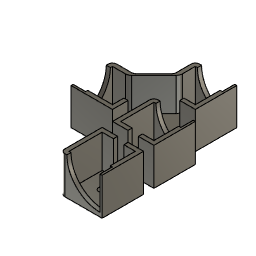
LedCorner15.5v13 (Autodesk Fusion 360 design; units mm, degrees)
Autodesk Fusion 360 part; units mm, degrees
sketch "Sketch1" plane through (0, 0, 0) normal (0, 0, 1) x (1, 0, 0)
  line L0 (0, 0) -> (20, 0)
  line L1 (20, 0) -> (20, 20)
  circle A0 centre (10, 10) radius 1.7
  line L2 (20, 10) -> (10, 10) construction
  line L3 (10, 0) -> (10, 10) construction
  line L4 (-4.9497, 4.9497) -> (0, 0)
  line L5 (12.5, 2) -> (12.5, 0)
  circle A1 centre (10, 10) radius 2.7
  line L6 (-0.5858, 9.3137) -> (-4.9497, 4.9497)
  line L7 (0, 18) -> (0, 10.7279)
  line L8 (2, 20) -> (20, 20)
  line L9 (18, 2) -> (18, 18)
  line L10 (2, 18) -> (18, 18)
  line L11 (2, 18) -> (2, 11.7279)
  line L12 (1.1213, 9.6066) -> (-4.2426, 4.2426)
  arc A2 (-0.5858, 9.3137) -> (0, 10.7279) centre (-2, 10.7279) ccw
  arc A3 (1.1213, 9.6066) -> (2, 11.7279) centre (-1, 11.7279) ccw
  line L13 (12.5, 2) -> (18, 2)
  arc A4 (2, 20) -> (0, 18) centre (2, 18) ccw
  line L14 (0, 13) -> (0, 0)
  line L15 (2, 13.8477) -> (2, 2)
  line L16 (2, 2) -> (7.5, 2)
  line L17 (7.5, 2) -> (7.5, 0)
  dimension "d4" = 3.4
  dimension "d28" = 2.5
  dimension "d29" = 135
  dimension "d33" = 1
  dimension "d35" = 7
  dimension "d49" = 2
  dimension "d50" = 3
  dimension "d52" = 2
  dimension "d53" = 2
  dimension "d54" = 20
  dimension "d55" = 20
  dimension "d57" = 2
  dimension "d58" = 2
  dimension "d59" = 1
  dimension "d60" = 2
  dimension "d67" = 2.5
  dimension "d68" = 2
  constraint coincident L0.start L4.end
  constraint horizontal L0
  constraint perpendicular L0 L1
  constraint midpoint L1 L2.start
  constraint coincident A0.centre L2.end
  constraint perpendicular L1 L2
  constraint midpoint L0 L3.start
  constraint perpendicular L0 L3
  constraint coincident L0 L5.end
  constraint perpendicular L0 L5
  constraint symmetric L6.end L4 L4.start
  constraint parallel L1 L9
  constraint parallel L8 L10
  constraint parallel L7 L11
  constraint parallel L6 L12
  constraint tangent L7 A2
  constraint tangent L6 A2
  constraint tangent L11 A3
  constraint tangent L12 A3
  constraint coincident L1.end L8.end
  constraint horizontal L8
  constraint tangent L8 A4
  constraint tangent L7 A4
  constraint perpendicular L4 L12
  constraint horizontal L13
  constraint coincident L4 L12.end
  constraint vertical L0.start L7.start
  constraint coincident L7 L14.start
  constraint perpendicular L0 L14
  constraint coincident L11 L15.start
  constraint perpendicular L13 L15
  constraint perpendicular L3 L16
  constraint perpendicular L0 L17
  constraint coincident L0 L17.end
  measures "d4" diameter of A0
  measures "d28" horizontal distance of A0.centre L5.start
  measures "d29" angle of L0 L4
  measures "d35" distance of L4.start L0.start
  measures "d49" radius of A2
  measures "d50" radius of A3
  measures "d52" distance of L5.start L5.end
  measures "d53" distance of L1 L9
  measures "d54" distance of L0.end L1.end
  measures "d55" distance of L1 L7
  measures "d57" distance of L8 L10
  measures "d58" distance of L7 L11
  measures "d59" distance of L6 L12
  measures "d60" radius of A4
  measures "d67" distance of L3 L16.end
  measures "d68" distance of L16.end L17.end
extrude "Extrude1" add sketch "Sketch1" along normal blind 2 contours L0 L12 A3 L14 L15 L16 L17 | L4 L12 L14 | L0 L5 L9 L10 L11 L13 L15 L16 L17 | L4 L6 L12 A2 L14 | L0 L1 L5 L7 L8 L9 L10 L11 L12 A3 L13 A4 L14 L15 | A1 makes body 1
extrude "Extrude2" add sketch "Sketch1" along normal blind 18 contours L4 L6 L12 A2 L14 | L0 L1 L5 L7 L8 L9 L10 L11 L12 A3 L13 A4 L14 L15 bodies 1
sketch "Sketch4" plane through (0, 20, 0) normal (0, 1, 0) x (-1, 0, 0)
  line L0 (-19, 18) -> (-19, 0.1056)
  arc A0 (-19, 2) -> (-3, 18) centre (-19, 18) ccw
  line L1 (-19, 18) -> (-3, 18)
  point P0 (-20, 18)
  dimension "d41" = 16
  dimension "d63" = 1
  constraint vertical L0
  constraint coincident L0 A0.start
  constraint coincident L0.start A0.centre
  constraint horizontal L1
  measures "d41" radius of A0
  measures "d63" distance of L0.start P0
extrude "Extrude7" cut sketch "Sketch4" against normal blind 6 bodies 1
mirror "Mirror1" about plane through (-4.2426, 4.2426, 0) normal (-0.707107, -0.707107, 0) of bodies 1 merged
chamfer "Chamfer2" distance 0.4 angle 45 11 edges at (0, 14.364, 0) (-0.1522, 9.9626, 0) (-4.9497, 4.9497, 0) (-9.9626, 0.1522, 0) (-14.364, 0, 0) (-19.4142, -0.5858, 0) (-20, -11, 0) (11, 20, 0) (0.5858, 19.4142, 0) (-10, -20, 0) (20, 10, 0) on bodies 1
fillet "Fillet2" radius 1 1 edges at (0, 0, 1) on bodies 1
copy_body "Body->Comp2" bodies 1 removing the originals makes body 2 in component "Corner"
move_body "Move1" bodies 2 to x (1, 0, 0) y (0, 1, 0) z (0, 0, 1) at (-5, 25, 0) in component "Corner"
extrude "Extrude8" add sketch "Sketch1" along normal blind 18 separate body contours L0 L12 A3 L14 L15 L16 L17 | L0 L1 L5 L7 L8 L9 L10 L11 L12 A3 L13 A4 L14 L15 makes body 3
extrude "Extrude11" add sketch "Sketch1" along normal blind 2 contours L0 L5 L9 L10 L11 L13 L15 L16 L17 | A1 bodies 3
extrude "Extrude10" cut sketch "Sketch4" against normal blind 6 bodies 3
mirror "Mirror2" about plane through (0, 0, 0) normal (0, -1, 0) of bodies 3 makes body 4
copy_body "Body->Comp3" bodies 3 removing the originals makes body 5 in component "EndR"
copy_body "Body->Comp5" bodies 4 removing the originals makes body 6 in component "EndL"
component "Corner" placed x (1, 0, 0) y (0, 1, 0) z (0, 0, 1) at (0, 0, 0)
component "EndR" placed x (1, 0, 0) y (0, 1, 0) z (0, 0, 1) at (0, 0, 0)
component "EndL" placed x (1, 0, 0) y (0, 1, 0) z (0, 0, 1) at (0, 0, 0)
